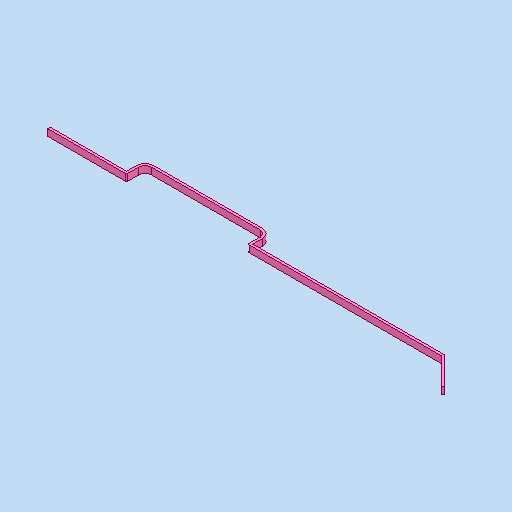
# Autodesk Inventor part: MM0861AN105_G11_302
Saved by Autodesk Inventor 2023.3 (Build 273359000, 359)
## iProperties
Part Number: MM0861AN105_G11_302
Material: Generisch
Description: =<RBPARTNOTITLE2>
Document SubType Name: Modeling
Designer: ric7an
Mass: 33.0842 g
Surface Area: 226.359 cm^2
Volume: 33.0842 cm^3
Density: 1 g/cm^3
Appearance: pink AnP
Vendor: Haewa
RBDOCUMENTTYPE: DRF
RBDOCUMENTVERSION: 00
RBDRAWINGMAINSCALE: 1:1
RBDRAWINGMISSINGSPEC: --
RBDRAWINGVOLUME: --
RBGBEDGESIN1: +0,5
RBGBEDGESIN2: +0,2
RBGBEDGESOUT1: -0,3
RBGBEDGESOUT2: -0,1
RBMATERIAL: --
RBMATMEETS: --
RBMATNO: =<Part Number>
RBPARTMADEOF: 3080-0102-18-00 / 0,8 m
RBPARTNO: SIEHE MNR
RBPARTNOTITLE1: gasket
RBPARTNOTITLE2: Dichtungsgummi selbstklebend
RBPARTSAFETYINDICATOR: --
RBSURFACE: --
RBSURFACE2: --
RBZEDGESNORM: ISO13715:2002-06
RBZGENDIMCLASS: m
RBZGENDIMNORM: ISO 2768-1:1989-11
RBZGENGEOCLASS: H
RBZGENGEONORM: ISO 2768-2:1989-11
RBZSURFACENORM: ISO13D2:2002-02
RBZTOLERANCENORM: ISO 14405-1:2010-12
AnP_Material: =<Material>
AnP_TemplVers: 20190222
AnP_Kategorie: 2
Author: ric7an
Keywords: =<RBPARTMADEOF>
Comments: =<RBSURFACE2>
Revision Number: 01
Autodesk Inventor part; units mm, degrees
ref_plane "YZ Plane" through (0, 0, 0) normal (1, 0, 0) x (0, 1, 0)
ref_plane "XZ Plane" through (0, 0, 0) normal (0, 1, 0) x (-1, 0, 0)
ref_plane "XY Plane" through (0, 0, 0) normal (0, 0, 1) x (1, 0, 0)
sketch "Skizze1" plane through (0, 0, 0) normal (0, 0, 1) x (1, 0, 0)
  line L0 (-137.1813, 0) -> (823.0876, 0) projected
  line L1 (0, 0) -> (124, 0)
  line L2 (124, 0) -> (124, 16)
  arc A0 (138, 30) -> (124, 16) centre (138, 16) ccw
  line L3 (138, 30) -> (315, 30)
  arc A1 (329, 16) -> (315, 30) centre (315, 16) ccw
  line L4 (329, 16) -> (329, 0)
  line L5 (329, 0) -> (641.5, 0)
  line L6 (641.5, 0) -> (685.9063, -44.4063)
  line L7 (0, 48.3607) -> (0, -59.8675) projected
  dimension "d13" = 124
  dimension "d14" = 30
  dimension "d15" = 205
  dimension "d16" = 312.5
  dimension "d17" = 14
  dimension "d18" = 14
  dimension "d19" = 641.5
  dimension "d20" = 135
  dimension "d21" = 62.8
  constraints: 12 end point, 4 point on circle, 4 tangent, 3 perpendicular, 3 point on line, 2 centre point, 1 collinear, 1 horizontal
  measures "d13" distance of L1.start L1.end
  measures "d14" distance between parallel lines of L1 L3
  measures "d15" distance from line of L4.end L2
  measures "d16" distance from line of L4 L5.end
  measures "d17" radius of A0
  measures "d18" radius of A1
  measures "d19" distance of L5.end L1.start
  measures "d20" angle of L6 L5
  measures "d21" distance of L5.end L6.end
sketch "Skizze2" plane through (0, 0, 0) normal (1, 0, 0) x (0, 1, 0)
  line L0 (0, 0) -> (-4, 0)
  line L1 (-4, 0) -> (-4, 11)
  line L2 (-4, 11) -> (0, 11)
  line L3 (0, 11) -> (0, 0)
  dimension "d6" = 4
  dimension "d7" = 11
  constraints: 8 end point, 2 parallel, 1 horizontal, 1 perpendicular
  measures "d6" distance of L1.end L2.end
  measures "d7" distance of L0.end L1.end
sweep "Sweeping1" add profiles "Skizze2" path "Skizze1" path curves L1 L2 A0 L3 A1 L4 L5 L6
fillet "Rundung1" radius 2 2 edges at (128, -4, 5.5) (325, -4, 5.5)
equation "\"d18\" = d17"
